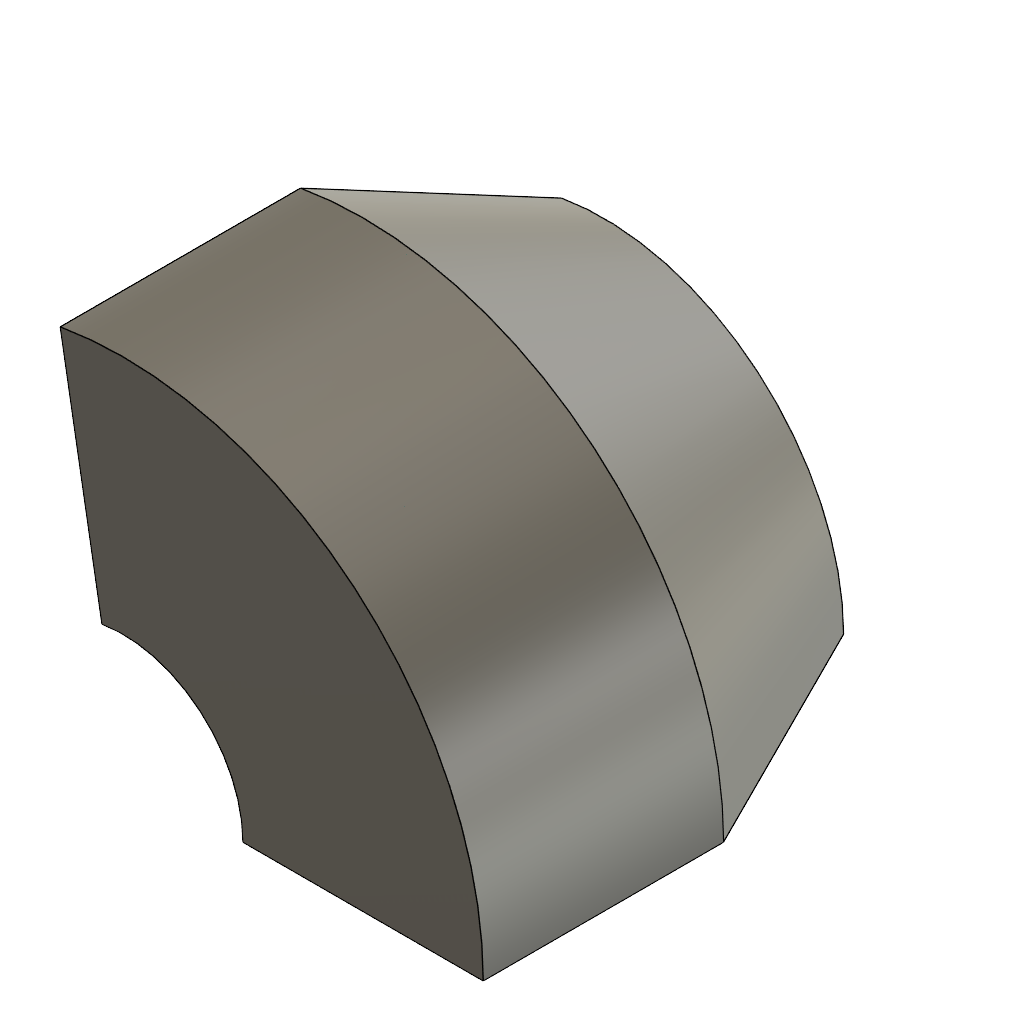
rev_partial_angle (Autodesk Fusion 360 design; units mm, degrees)
part number: 2026-11-13-14-37-11-062
Autodesk Fusion 360 part; units mm, degrees
sketch "Sketch1" plane through (0, 0, 0) normal (0, 1, 0) x (1, 0, 0)
  line L0 (5, 0) -> (15, 0)
  line L1 (15, 0) -> (15, 10)
  line L2 (15, 10) -> (10, 20)
  line L3 (10, 20) -> (5, 20)
  line L4 (5, 20) -> (5, 0)
revolve "Revolve1" add sketch "Sketch1" angle 100 about axis through (0, 0, 1.75) along (0, 0, 1)
